Autodesk Fusion 360 part; units mm, degrees
(part 3 of 18)
  line L916 (69.5484, -103.959) -> (68.9847, -104.146)
  line L917 (27.4521, -121.483) -> (28.0455, -121.505)
  line L918 (185.518, -120.817) -> (186.059, -120.571)
  line L919 (19.2578, -114.105) -> (19.3803, -114.686)
  line L920 (174.55, -117.401) -> (174.888, -117.889)
  line L921 (174.245, -116.891) -> (174.55, -117.401)
  line L922 (180.861, -121.422) -> (181.452, -121.483)
  line L923 (179.699, -121.183) -> (180.276, -121.322)
  line L924 (70.7068, -103.7) -> (70.1233, -103.811)
  line L925 (180.276, -121.322) -> (180.861, -121.422)
  line L926 (19.3803, -114.686) -> (19.541, -115.258)
  line L927 (64.17, -108.346) -> (63.9088, -108.879)
  line L928 (29.8346, -121.428) -> (29.2581, -121.523)
  line L929 (183.663, -103.737) -> (183.075, -103.651)
  line L930 (28.0926, -121.6) -> (27.5085, -121.582)
  line L931 (184.243, -103.861) -> (183.663, -103.737)
  line L932 (176.417, -105.61) -> (175.97, -106.001)
  line L933 (176.889, -105.251) -> (176.417, -105.61)
  line L934 (177.385, -104.923) -> (176.889, -105.251)
  line L935 (19.3817, -115.06) -> (19.2379, -114.493)
  line L936 (27.5085, -121.582) -> (26.9269, -121.527)
  line L937 (64.7955, -107.337) -> (64.466, -107.831)
  line L938 (188.753, -106.581) -> (188.342, -106.152)
  line L939 (182.093, -121.6) -> (181.509, -121.582)
  line L940 (182.677, -121.58) -> (182.093, -121.6)
  line L941 (29.8162, -121.334) -> (30.3945, -121.2)
  line L942 (180.35, -121.434) -> (179.78, -121.304)
  line L943 (180.927, -121.527) -> (180.35, -121.434)
  line L944 (181.509, -121.582) -> (180.927, -121.527)
  line L945 (76.4456, -104.733) -> (75.9179, -104.461)
  line L946 (33.9903, -119.401) -> (33.5358, -119.768)
  line L947 (173.562, -115.616) -> (173.382, -115.06)
  line L948 (63.2379, -114.493) -> (63.1309, -113.919)
  line L949 (21.8816, -105.953) -> (22.3203, -105.567)
  line L950 (63.1309, -113.919) -> (63.0612, -113.339)
  line L951 (35.8585, -117.17) -> (35.5441, -117.663)
  line L952 (32.0441, -120.684) -> (31.5109, -120.923)
  line L953 (72.0926, -121.6) -> (71.5085, -121.582)
  line L954 (72.6766, -121.58) -> (72.0926, -121.6)
  line L955 (19.541, -115.258) -> (19.7392, -115.817)
  line L956 (189.133, -107.037) -> (188.753, -106.581)
  line L957 (181.889, -103.597) -> (181.296, -103.629)
  line L958 (182.483, -103.604) -> (181.889, -103.597)
  line L959 (183.075, -103.651) -> (182.483, -103.604)
  line L960 (173.238, -114.493) -> (173.131, -113.919)
  line L961 (173.382, -115.06) -> (173.238, -114.493)
  line L962 (175.657, -118.793) -> (176.085, -119.205)
  line L963 (174.888, -117.889) -> (175.257, -118.354)
  line L964 (72.483, -103.604) -> (71.8893, -103.597)
  line L965 (175.257, -118.354) -> (175.657, -118.793)
  line L966 (19.1309, -113.919) -> (19.0612, -113.339)
  line L967 (28.0455, -121.505) -> (28.6391, -121.487)
  line L968 (179.22, -121.137) -> (178.672, -120.935)
  line L969 (179.78, -121.304) -> (179.22, -121.137)
  line L970 (173.061, -113.339) -> (173.029, -112.755)
  line L971 (173.131, -113.919) -> (173.061, -113.339)
  line L972 (173.029, -112.755) -> (173.033, -112.331)
  line L973 (74.2432, -103.861) -> (73.6626, -103.737)
  line L974 (24.672, -120.935) -> (24.138, -120.698)
  line L975 (19.7774, -116.159) -> (19.5618, -115.616)
  line L976 (189.544, -117.663) -> (189.199, -118.134)
  line L977 (65.7561, -119.027) -> (65.3513, -118.606)
  line L978 (66.1873, -119.421) -> (65.7561, -119.027)
  line L979 (65.3513, -118.606) -> (64.9746, -118.159)
  line L980 (21.0836, -106.806) -> (21.4688, -106.366)
  line L981 (30.4039, -121.296) -> (29.8346, -121.428)
  line L982 (36.8266, -110.238) -> (36.9575, -110.808)
  line L983 (77.5358, -119.768) -> (77.0587, -120.105)
  line L984 (70.35, -121.434) -> (69.7803, -121.304)
  line L985 (70.9269, -121.527) -> (70.35, -121.434)
  line L986 (77.9903, -119.401) -> (77.5358, -119.768)
  line L987 (71.5085, -121.582) -> (70.9269, -121.527)
  line L988 (20.402, -107.754) -> (20.7274, -107.269)
  line L989 (36.6591, -109.678) -> (36.8266, -110.238)
  line L990 (36.4559, -109.131) -> (36.6591, -109.678)
  line L991 (80.7806, -115.029) -> (80.6024, -115.586)
  line L992 (80.9224, -114.462) -> (80.7806, -115.029)
  line L993 (76.0441, -120.684) -> (75.5109, -120.923)
  line L994 (76.5607, -120.411) -> (76.0441, -120.684)
  line L995 (77.0587, -120.105) -> (76.5607, -120.411)
  line L996 (19.8482, -108.783) -> (20.1085, -108.26)
  line L997 (31.5109, -120.923) -> (30.9634, -121.127)
  line L998 (80.6591, -109.678) -> (80.8266, -110.238)
  line L999 (30.9634, -121.127) -> (30.4039, -121.296)
  line L1000 (80.4559, -109.131) -> (80.6591, -109.678)
  line L1001 (80.3887, -116.13) -> (80.1404, -116.659)
  line L1002 (80.6024, -115.586) -> (80.3887, -116.13)
  line L1003 (80.1404, -116.659) -> (79.8585, -117.17)
  line L1004 (19.4315, -109.874) -> (19.6222, -109.322)
  line L1005 (22.539, -119.587) -> (23.0175, -119.939)
  line L1006 (23.0175, -119.939) -> (23.5183, -120.258)
  line L1007 (77.2028, -105.092) -> (77.6734, -105.438)
  line L1008 (81.0514, -111.384) -> (81.1079, -111.966)
  line L1009 (80.9575, -110.808) -> (81.0514, -111.384)
  line L1010 (76.7108, -104.776) -> (77.2028, -105.092)
  line L1011 (80.8266, -110.238) -> (80.9575, -110.808)
  line L1012 (23.5183, -120.258) -> (24.0392, -120.543)
  line L1013 (19.0612, -113.339) -> (19.0291, -112.755)
  line L1014 (19.1589, -111.01) -> (19.2769, -110.437)
  line L1015 (71.682, -103.509) -> (72.2663, -103.502)
  line L1016 (71.0994, -103.553) -> (71.682, -103.509)
  line L1017 (78.5428, -106.218) -> (78.9379, -106.649)
  line L1018 (78.1207, -105.814) -> (78.5428, -106.218)
  line L1019 (63.1297, -112.925) -> (63.1742, -113.517)
  line L1020 (19.0291, -112.755) -> (19.0332, -112.331)
  line L1021 (77.6734, -105.438) -> (78.1207, -105.814)
  line L1022 (24.0392, -120.543) -> (24.5778, -120.793)
  line L1023 (66.3203, -105.567) -> (66.7829, -105.21)
  line L1024 (65.8816, -105.953) -> (66.3203, -105.567)
  line L1025 (73.4301, -103.602) -> (74.0047, -103.708)
  line L1026 (72.2663, -103.502) -> (72.8498, -103.533)
  line L1027 (63.1587, -111.738) -> (63.1245, -112.331)
  line L1028 (72.8498, -103.533) -> (73.4301, -103.602)
  line L1029 (63.2769, -110.437) -> (63.4315, -109.874)
  line L1030 (63.1589, -111.01) -> (63.2769, -110.437)
  line L1031 (67.7724, -104.589) -> (68.2951, -104.328)
  line L1032 (67.2676, -104.884) -> (67.7724, -104.589)
  line L1033 (66.7829, -105.21) -> (67.2676, -104.884)
  line L1034 (63.3443, -110.566) -> (63.232, -111.149)
  line L1035 (19.0347, -112.171) -> (19.078, -111.588)
  line L1036 (173.909, -108.879) -> (173.683, -109.429)
  line L1037 (19.0332, -112.331) -> (19.0347, -112.171)
  line L1038 (174.17, -108.346) -> (173.909, -108.879)
  line L1039 (63.6222, -109.322) -> (63.8482, -108.783)
  line L1040 (63.4315, -109.874) -> (63.6222, -109.322)
  line L1041 (63.8482, -108.783) -> (64.1085, -108.26)
  line L1042 (37.1079, -64.566) -> (37.1268, -65.15)
  line L1043 (36.8847, -66.7665) -> (36.9725, -66.1793)
  line L1044 (36.7582, -67.3467) -> (36.8847, -66.7665)
  line L1045 (33.0844, -72.574) -> (33.5654, -72.2258)
  line L1046 (35.8785, -69.546) -> (36.1527, -69.0193)
  line L1047 (36.7806, -67.6293) -> (36.6024, -68.1858)
  line L1048 (25.2202, -73.7373) -> (24.672, -73.5351)
  line L1049 (35.5441, -70.263) -> (35.1986, -70.7342)
  line L1050 (35.8585, -69.7704) -> (35.5441, -70.263)
  line L1051 (36.9575, -63.4077) -> (37.0514, -63.9844)
  line L1052 (28.6766, -74.1801) -> (28.0926, -74.2)
  line L1053 (36.1404, -69.2586) -> (35.8585, -69.7704)
  line L1054 (37.0514, -63.9844) -> (37.1079, -64.566)
  line L1055 (29.2581, -74.1226) -> (28.6766, -74.1801)
  line L1056 (27.5085, -74.1821) -> (26.9269, -74.1266)
  line L1057 (30.9634, -73.7273) -> (30.4039, -73.8957)
  line L1058 (32.0441, -73.2841) -> (31.5109, -73.5231)
  line L1059 (33.6734, -58.038) -> (34.1207, -58.414)
  line L1060 (36.6591, -62.2784) -> (36.8266, -62.8382)
  line L1061 (28.0926, -74.2) -> (27.5085, -74.1821)
  line L1062 (29.8346, -74.0276) -> (29.2581, -74.1226)
  line L1063 (20.3113, -69.7975) -> (20.0276, -69.2867)
  line L1064 (23.6204, -73.0267) -> (23.1214, -72.7227)
  line L1065 (35.3045, -59.7036) -> (35.6409, -60.1813)
  line L1066 (25.3856, -56.5094) -> (25.9488, -56.3538)
  line L1067 (37.0951, -65.9073) -> (37.0274, -66.4877)
  line L1068 (36.1527, -69.0193) -> (36.3914, -68.4756)
  line L1069 (36.9224, -67.0625) -> (36.7806, -67.6293)
  line L1070 (37.0274, -66.4877) -> (36.9224, -67.0625)
  line L1071 (36.8266, -62.8382) -> (36.9575, -63.4077)
  line L1072 (25.9488, -56.3538) -> (26.5208, -56.2348)
  line L1073 (30.0047, -56.3077) -> (30.5713, -56.4506)
  line L1074 (19.8482, -61.3827) -> (20.1085, -60.8595)
  line L1075 (20.402, -60.3542) -> (20.7274, -59.869)
  line L1076 (34.5428, -58.818) -> (34.9379, -59.2485)
  line L1077 (22.1873, -72.0214) -> (21.7561, -71.627)
  line L1078 (36.6024, -68.1858) -> (36.3887, -68.7297)
  line L1079 (20.6274, -70.289) -> (20.3113, -69.7975)
  line L1080 (20.1085, -60.8595) -> (20.402, -60.3542)
  line L1081 (30.4039, -73.8957) -> (29.8346, -74.0276)
  line L1082 (27.682, -56.1086) -> (28.2663, -56.102)
  line L1083 (33.9903, -72.0008) -> (33.5358, -72.3681)
  line L1084 (35.1986, -70.7342) -> (34.8234, -71.1821)
  line L1085 (32.0585, -73.1711) -> (32.5813, -72.8896)
  line L1086 (24.8336, -56.7011) -> (25.3856, -56.5094)
  line L1087 (26.35, -74.0337) -> (25.7803, -73.9038)
  line L1088 (37.1268, -65.15) -> (37.1251, -65.3237)
  line L1089 (23.1214, -72.7227) -> (22.643, -72.3871)
  line L1090 (21.7561, -71.627) -> (21.3513, -71.2056)
  line L1091 (25.7803, -73.9038) -> (25.2202, -73.7373)
  line L1092 (35.6409, -60.1813) -> (35.9457, -60.6798)
  line L1093 (36.2178, -61.1969) -> (36.4559, -61.7305)
  line L1094 (21.3513, -71.2056) -> (20.9746, -70.759)
  line L1095 (19.7774, -68.7587) -> (19.5618, -68.2156)
  line L1096 (32.5607, -73.0111) -> (32.0441, -73.2841)
  line L1097 (36.3914, -68.4756) -> (36.5935, -67.9172)
  line L1098 (32.5813, -72.8896) -> (33.0844, -72.574)
  line L1099 (34.42, -71.6049) -> (33.9903, -72.0008)
  line L1100 (34.453, -71.4378) -> (34.8557, -71.0014)
  line L1101 (36.9725, -66.1793) -> (37.0211, -65.5875)
  line L1102 (26.9269, -74.1266) -> (26.35, -74.0337)
  line L1103 (34.0223, -71.8465) -> (34.453, -71.4378)
  line L1104 (31.5109, -73.5231) -> (30.9634, -73.7273)
  line L1105 (26.8615, -74.0221) -> (27.4521, -74.0832)
  line L1106 (109.882, -58.5528) -> (110.32, -58.1668)
  line L1107 (159.296, -56.2291) -> (158.707, -56.3004)
  line L1108 (19.541, -67.8577) -> (19.7392, -68.4175)
  line L1109 (33.5654, -72.2258) -> (34.0223, -71.8465)
  line L1110 (107.622, -61.9215) -> (107.848, -61.3827)
  line L1111 (27.0994, -56.1529) -> (27.682, -56.1086)
  line L1112 (25.6987, -73.7835) -> (26.2761, -73.9221)
  line L1113 (19.3817, -67.6597) -> (19.2379, -67.0934)
  line L1114 (24.138, -73.2979) -> (23.6204, -73.0267)
  line L1115 (19.5618, -68.2156) -> (19.3817, -67.6597)
  line L1116 (35.2286, -70.5393) -> (35.57, -70.0534)
  line L1117 (26.5208, -56.2348) -> (27.0994, -56.1529)
  line L1118 (36.3887, -68.7297) -> (36.1404, -69.2586)
  line L1119 (35.57, -70.0534) -> (35.8785, -69.546)
  line L1120 (32.1995, -57.0936) -> (32.7108, -57.3764)
  line L1121 (20.0276, -69.2867) -> (19.7774, -68.7587)
  line L1122 (37.1251, -65.3237) -> (37.0951, -65.9073)
  line L1123 (22.643, -72.3871) -> (22.1873, -72.0214)
  line L1124 (33.0587, -72.7054) -> (32.5607, -73.0111)
  line L1125 (36.5935, -67.9172) -> (36.7582, -67.3467)
  line L1126 (34.8234, -71.1821) -> (34.42, -71.6049)
  line L1127 (34.8557, -71.0014) -> (35.2286, -70.5393)
  line L1128 (19.0347, -64.771) -> (19.078, -64.1883)
  line L1129 (33.5358, -72.3681) -> (33.0587, -72.7054)
  line L1130 (20.9746, -70.759) -> (20.6274, -70.289)
  line L1131 (35.4833, -60.1165) -> (35.1334, -59.6368)
  line L1132 (24.672, -73.5351) -> (24.138, -73.2979)
  line L1133 (19.0332, -64.9312) -> (19.0347, -64.771)
  line L1134 (19.1742, -66.1171) -> (19.2578, -66.705)
  line L1135 (109.469, -58.9664) -> (109.882, -58.5528)
  line L1136 (19.1309, -66.5189) -> (19.0612, -65.9388)
  line L1137 (107.848, -61.3827) -> (108.108, -60.8595)
  line L1138 (29.8162, -73.9345) -> (30.3945, -73.7999)
  line L1139 (19.0291, -65.3553) -> (19.0332, -64.9312)
  line L1140 (19.0612, -65.9388) -> (19.0291, -65.3553)
  line L1141 (28.6391, -74.0873) -> (29.2302, -74.0304)
  line L1142 (27.4521, -74.0832) -> (28.0455, -74.1049)
  line L1143 (19.2578, -66.705) -> (19.3803, -67.2861)
  line L1144 (35.1334, -59.6368) -> (34.7525, -59.1812)
  line L1145 (19.7392, -68.4175) -> (19.9741, -68.9629)
  line L1146 (19.9741, -68.9629) -> (20.2446, -69.4915)
  line L1147 (20.5495, -70.001) -> (20.8876, -70.4892)
  line L1148 (108.727, -59.869) -> (109.084, -59.4057)
  line L1149 (21.2572, -70.9539) -> (21.6569, -71.3931)
  line L1150 (37.0121, -64.5565) -> (36.9531, -63.9656)
  line L1151 (36.9531, -63.9656) -> (36.8551, -63.38)
  line L1152 (109.084, -59.4057) -> (109.469, -58.9664)
  line L1153 (30.8143, -56.6237) -> (30.2432, -56.461)
  line L1154 (20.2446, -69.4915) -> (20.5495, -70.001)
  line L1155 (36.084, -61.1403) -> (35.8006, -60.6185)
  line L1156 (32.954, -57.6397) -> (32.4456, -57.333)
  line L1157 (21.6569, -71.3931) -> (22.0847, -71.8049)
  line L1158 (33.9045, -58.3507) -> (33.4411, -57.9794)
  line L1159 (107.432, -62.4738) -> (107.622, -61.9215)
  line L1160 (19.2379, -67.0934) -> (19.1309, -66.5189)
  line L1161 (36.8551, -63.38) -> (36.7185, -62.8021)
  line L1162 (27.8893, -56.197) -> (27.2963, -56.2291)
  line L1163 (30.2432, -56.461) -> (29.6626, -56.3365)
  line L1164 (108.402, -60.3542) -> (108.727, -59.869)
  line L1165 (32.4456, -57.333) -> (31.9179, -57.0606)
  line L1166 (153.97, -58.6007) -> (153.549, -59.0199)
  line L1167 (26.7068, -56.3004) -> (26.1233, -56.4107)
  line L1168 (24.4345, -56.9692) -> (23.9003, -57.2286)
  line L1169 (151.232, -63.7491) -> (151.159, -64.3384)
  line L1170 (19.2769, -63.0373) -> (19.4315, -62.4738)
  line L1171 (155.385, -57.5228) -> (154.889, -57.8505)
  line L1172 (158.123, -56.4107) -> (157.548, -56.5593)
  line L1173 (153.549, -59.0199) -> (153.157, -59.466)
  line L1174 (26.1233, -56.4107) -> (25.5484, -56.5593)
  line L1175 (157.548, -56.5593) -> (156.985, -56.7458)
  line L1176 (19.6222, -61.9215) -> (19.8482, -61.3827)
  line L1177 (108.108, -60.8595) -> (108.402, -60.3542)
  line L1178 (19.4315, -62.4738) -> (19.6222, -61.9215)
  line L1179 (152.795, -59.9371) -> (152.466, -60.4311)
  line L1180 (27.2963, -56.2291) -> (26.7068, -56.3004)
  line L1181 (23.3845, -57.5228) -> (22.8893, -57.8505)
  line L1182 (29.6626, -56.3365) -> (29.075, -56.2508)
  line L1183 (31.9179, -57.0606) -> (31.3734, -56.8239)
  line L1184 (151.124, -64.9312) -> (151.13, -65.525)
  line L1185 (23.9003, -57.2286) -> (23.3845, -57.5228)
  line L1186 (151.344, -63.166) -> (151.232, -63.7491)
  line L1187 (151.159, -64.3384) -> (151.124, -64.9312)
  line L1188 (22.8893, -57.8505) -> (22.417, -58.2104)
  line L1189 (31.3734, -56.8239) -> (30.8143, -56.6237)
  line L1190 (37.0318, -65.15) -> (37.0121, -64.5565)
  line L1191 (160.483, -56.2042) -> (159.889, -56.197)
  line L1192 (24.9847, -56.7458) -> (24.4345, -56.9692)
  line L1193 (25.5484, -56.5593) -> (24.9847, -56.7458)
  line L1194 (30.9627, -73.6272) -> (31.5182, -73.4173)
  line L1195 (23.0175, -72.5389) -> (23.5183, -72.8579)
  line L1196 (31.5182, -73.4173) -> (32.0585, -73.1711)
  line L1197 (29.2302, -74.0304) -> (29.8162, -73.9345)
  line L1198 (22.417, -58.2104) -> (21.9695, -58.6007)
  line L1199 (156.985, -56.7458) -> (156.434, -56.9692)
  line L1200 (22.0847, -71.8049) -> (22.539, -72.1873)
  line L1201 (151.495, -62.5917) -> (151.344, -63.166)
  line L1202 (28.483, -56.2042) -> (27.8893, -56.197)
  line L1203 (19.3443, -63.166) -> (19.232, -63.7491)
  line L1204 (19.232, -63.7491) -> (19.1587, -64.3384)
  line L1205 (30.3945, -73.7999) -> (30.9627, -73.6272)
  line L1206 (19.1297, -65.525) -> (19.1742, -66.1171)
  line L1207 (151.909, -61.4791) -> (151.683, -62.0285)
  line L1208 (19.495, -62.5917) -> (19.3443, -63.166)
  line L1209 (154.889, -57.8505) -> (154.417, -58.2104)
  line L1210 (153.157, -59.466) -> (152.795, -59.9371)
  line L1211 (26.2761, -73.9221) -> (26.8615, -74.0221)
  line L1212 (19.078, -64.1883) -> (19.1589, -63.6096)
  line L1213 (107.159, -63.6096) -> (107.277, -63.0373)
  line L1214 (19.1245, -64.9312) -> (19.1297, -65.525)
  line L1215 (20.7955, -59.9371) -> (20.466, -60.4311)
  line L1216 (152.466, -60.4311) -> (152.17, -60.9459)
  line L1217 (19.1587, -64.3384) -> (19.1245, -64.9312)
  line L1218 (19.1589, -63.6096) -> (19.2769, -63.0373)
  line L1219 (21.9695, -58.6007) -> (21.5489, -59.0199)
  line L1220 (151.683, -62.0285) -> (151.495, -62.5917)
  line L1221 (22.539, -72.1873) -> (23.0175, -72.5389)
  line L1222 (20.8876, -70.4892) -> (21.2572, -70.9539)
  line L1223 (107.277, -63.0373) -> (107.432, -62.4738)
  line L1224 (23.5183, -72.8579) -> (24.0392, -73.1431)
  line L1225 (25.1318, -73.6069) -> (25.6987, -73.7835)
  line L1226 (154.417, -58.2104) -> (153.97, -58.6007)
  line L1227 (158.707, -56.3004) -> (158.123, -56.4107)
  line L1228 (21.157, -59.466) -> (20.7955, -59.9371)
  line L1229 (21.5489, -59.0199) -> (21.157, -59.466)
  line L1230 (152.17, -60.9459) -> (151.909, -61.4791)
  line L1231 (34.3423, -58.7519) -> (33.9045, -58.3507)
  line L1232 (28.0455, -74.1049) -> (28.6391, -74.0873)
  line L1233 (24.5778, -73.3931) -> (25.1318, -73.6069)
  line L1234 (34.7525, -59.1812) -> (34.3423, -58.7519)
  line L1235 (23.2676, -57.4835) -> (23.7724, -57.1892)
  line L1236 (29.4301, -56.2018) -> (30.0047, -56.3077)
  line L1237 (31.671, -56.8443) -> (32.1995, -57.0936)
  line L1238 (24.0392, -73.1431) -> (24.5778, -73.3931)
  line L1239 (19.3803, -67.2861) -> (19.541, -67.8577)
  line L1240 (107.078, -64.1883) -> (107.159, -63.6096)
  line L1241 (33.4411, -57.9794) -> (32.954, -57.6397)
  line L1242 (34.1207, -58.414) -> (34.5428, -58.818)
  line L1243 (28.2663, -56.102) -> (28.8498, -56.1331)
  line L1244 (31.1275, -56.6297) -> (31.671, -56.8443)
  line L1245 (110.32, -58.1668) -> (110.783, -57.8099)
  line L1246 (36.4559, -61.7305) -> (36.6591, -62.2784)
  line L1247 (34.9379, -59.2485) -> (35.3045, -59.7036)
  line L1248 (22.7829, -57.8099) -> (23.2676, -57.4835)
  line L1249 (35.9457, -60.6798) -> (36.2178, -61.1969)
  line L1250 (30.5713, -56.4506) -> (31.1275, -56.6297)
  line L1251 (28.8498, -56.1331) -> (29.4301, -56.2018)
  line L1252 (21.4688, -58.9664) -> (21.8816, -58.5528)
  line L1253 (21.8816, -58.5528) -> (22.3203, -58.1668)
  line L1254 (155.9, -57.2286) -> (155.385, -57.5228)
  line L1255 (36.3321, -61.6798) -> (36.084, -61.1403)
  line L1256 (35.8006, -60.6185) -> (35.4833, -60.1165)
  line L1257 (33.2028, -57.6917) -> (33.6734, -58.038)
  line L1258 (22.3203, -58.1668) -> (22.7829, -57.8099)
  line L1259 (20.7274, -59.869) -> (21.0836, -59.4057)
  line L1260 (21.0836, -59.4057) -> (21.4688, -58.9664)
  line L1261 (36.5439, -62.2345) -> (36.3321, -61.6798)
  line L1262 (36.7185, -62.8021) -> (36.5439, -62.2345)
  line L1263 (32.7108, -57.3764) -> (33.2028, -57.6917)
  line L1264 (159.889, -56.197) -> (159.296, -56.2291)
  line L1265 (24.2951, -56.928) -> (24.8336, -56.7011)
  line L1266 (23.7724, -57.1892) -> (24.2951, -56.928)
  line L1267 (29.075, -56.2508) -> (28.483, -56.2042)
  line L1268 (37.0211, -65.5875) -> (37.0318, -65.15)
  line L1269 (151.13, -65.525) -> (151.174, -66.1171)
  line L1270 (156.434, -56.9692) -> (155.9, -57.2286)
  line L1271 (52.4039, -50.1957) -> (51.8346, -50.3276)
  line L1272 (156.138, -49.5979) -> (155.62, -49.3267)
  line L1273 (156.672, -49.8351) -> (156.138, -49.5979)
  line L1274 (80.5439, -38.5345) -> (80.3321, -37.9798)
  line L1275 (76.954, -33.9397) -> (76.4456, -33.633)
  line L1276 (75.9179, -33.3606) -> (75.3734, -33.1239)
  line L1277 (56.42, -47.9049) -> (55.9903, -48.3008)
  line L1278 (153.882, -34.8528) -> (154.32, -34.4668)
  line L1279 (154.32, -34.4668) -> (154.783, -34.1099)
  line L1280 (163.671, -33.1443) -> (164.199, -33.3936)
  line L1281 (58.2178, -37.4969) -> (58.4559, -38.0305)
  line L1282 (160.677, -50.4801) -> (160.093, -50.5)
  line L1283 (72.0926, -50.5) -> (71.5085, -50.4821)
  line L1284 (78.3423, -35.0519) -> (77.9045, -34.6507)
  line L1285 (42.0276, -45.5867) -> (41.7774, -45.0587)
  line L1286 (58.7806, -43.9293) -> (58.6024, -44.4858)
  line L1287 (73.075, -32.5508) -> (72.483, -32.5042)
  line L1288 (79.5441, -46.563) -> (79.1986, -47.0342)
  line L1289 (69.5484, -32.8593) -> (68.9847, -33.0458)
  line L1290 (167.544, -46.563) -> (167.199, -47.0342)
  line L1291 (70.7068, -32.6004) -> (70.1233, -32.7107)
  line L1292 (166.121, -34.714) -> (166.543, -35.118)
  line L1293 (168.218, -37.4969) -> (168.456, -38.0305)
  line L1294 (51.2581, -50.4226) -> (50.6766, -50.4801)
  line L1295 (73.6626, -32.6365) -> (73.075, -32.5508)
  line L1296 (65.2572, -47.2539) -> (65.6569, -47.6931)
  line L1297 (79.8585, -46.0704) -> (79.5441, -46.563)
  line L1298 (59.0514, -40.2844) -> (59.1079, -40.866)
  line L1299 (55.5358, -48.6681) -> (55.0587, -49.0054)
  line L1300 (51.075, -32.5508) -> (50.483, -32.5042)
  line L1301 (46.9847, -33.0458) -> (46.4345, -33.2692)
  line L1302 (58.6591, -38.5784) -> (58.8266, -39.1382)
  line L1303 (52.8143, -32.9237) -> (52.2432, -32.761)
  line L1304 (63.232, -40.0491) -> (63.1587, -40.6384)
  line L1305 (164.199, -33.3936) -> (164.711, -33.6764)
  line L1306 (56.8557, -47.3014) -> (57.2286, -46.8393)
  line L1307 (47.7803, -50.2038) -> (47.2202, -50.0373)
  line L1308 (54.954, -33.9397) -> (54.4456, -33.633)
  line L1309 (167.858, -46.0704) -> (167.544, -46.563)
  line L1310 (54.5607, -49.3111) -> (54.0441, -49.5841)
  line L1311 (55.9045, -34.6507) -> (55.4411, -34.2794)
  line L1312 (59.0274, -42.7877) -> (58.9224, -43.3625)
  line L1313 (78.7525, -35.4812) -> (78.3423, -35.0519)
  line L1314 (165.203, -33.9917) -> (165.673, -34.338)
  line L1315 (80.3887, -45.0297) -> (80.1404, -45.5586)
  line L1316 (164.711, -33.6764) -> (165.203, -33.9917)
  line L1317 (163.128, -32.9297) -> (163.671, -33.1443)
  line L1318 (57.5441, -46.563) -> (57.1986, -47.0342)
  line L1319 (52.9634, -50.0273) -> (52.4039, -50.1957)
  line L1320 (59.0951, -42.2073) -> (59.0274, -42.7877)
  line L1321 (157.386, -32.8094) -> (157.949, -32.6538)
  line L1322 (63.1742, -42.4171) -> (63.2578, -43.005)
  line L1323 (69.6987, -50.0835) -> (70.2761, -50.2221)
  line L1324 (58.7582, -43.6467) -> (58.8847, -43.0665)
  line L1325 (75.1275, -32.9297) -> (75.671, -33.1443)
  line L1326 (166.543, -35.118) -> (166.938, -35.5485)
  line L1327 (80.8266, -39.1382) -> (80.9575, -39.7077)
  line L1328 (63.1245, -41.2312) -> (63.1297, -41.825)
  line L1329 (58.9224, -43.3625) -> (58.7806, -43.9293)
  line L1330 (72.483, -32.5042) -> (71.8893, -32.497)
  line L1331 (53.9179, -33.3606) -> (53.3734, -33.1239)
  line L1332 (66.1873, -48.3214) -> (65.7561, -47.927)
  line L1333 (59.1251, -41.6237) -> (59.0951, -42.2073)
  line L1334 (64.7955, -36.2371) -> (64.466, -36.7311)
  line L1335 (76.4456, -33.633) -> (75.9179, -33.3606)
  line L1336 (58.3887, -45.0297) -> (58.1404, -45.5586)
  line L1337 (54.4456, -33.633) -> (53.9179, -33.3606)
  line L1338 (165.673, -34.338) -> (166.121, -34.714)
  line L1339 (45.6204, -49.3267) -> (45.1214, -49.0227)
  line L1340 (55.4411, -34.2794) -> (54.954, -33.9397)
  line L1341 (44.643, -48.6871) -> (44.1873, -48.3214)
  line L1342 (162.005, -32.6077) -> (162.571, -32.7506)
  line L1343 (58.3914, -44.7756) -> (58.5935, -44.2172)
  line L1344 (168.391, -44.7756) -> (168.594, -44.2172)
  line L1345 (43.3513, -47.5056) -> (42.9746, -47.059)
  line L1346 (151.848, -37.6827) -> (152.108, -37.1595)
  line L1347 (68.8336, -33.0011) -> (69.3856, -32.8094)
  line L1348 (81.1079, -40.866) -> (81.1268, -41.45)
  line L1349 (162.571, -32.7506) -> (163.128, -32.9297)
  line L1350 (80.084, -37.4403) -> (79.8006, -36.9185)
  line L1351 (168.758, -43.6467) -> (168.885, -43.0665)
  line L1352 (46.4345, -33.2692) -> (45.9003, -33.5286)
  line L1353 (74.9627, -49.9272) -> (75.5182, -49.7173)
  line L1354 (152.727, -36.169) -> (153.084, -35.7057)
  line L1355 (63.495, -38.8917) -> (63.3443, -39.466)
  line L1356 (58.9725, -42.4793) -> (59.0211, -41.8875)
  line L1357 (63.7774, -45.0587) -> (63.5618, -44.5156)
  line L1358 (79.6409, -36.4813) -> (79.9457, -36.9798)
  line L1359 (151.562, -44.5156) -> (151.382, -43.9597)
  line L1360 (74.2432, -32.761) -> (73.6626, -32.6365)
  line L1361 (79.1334, -35.9368) -> (78.7525, -35.4812)
  line L1362 (78.1207, -34.714) -> (78.5428, -35.118)
  line L1363 (41.9741, -45.2629) -> (42.2446, -45.7915)
  line L1364 (168.957, -39.7077) -> (169.051, -40.2844)
  line L1365 (54.0585, -49.4711) -> (54.5813, -49.1896)
  line L1366 (79.1986, -47.0342) -> (78.8234, -47.4821)
  line L1367 (53.5109, -49.8231) -> (52.9634, -50.0273)
  line L1368 (75.3734, -33.1239) -> (74.8143, -32.9237)
  line L1369 (77.9045, -34.6507) -> (77.4411, -34.2794)
  line L1370 (76.0441, -49.5841) -> (75.5109, -49.8231)
  line L1371 (48.7068, -32.6004) -> (48.1233, -32.7107)
  line L1372 (45.9003, -33.5286) -> (45.3845, -33.8228)
  line L1373 (50.6391, -50.3873) -> (51.2302, -50.3304)
  line L1374 (168.922, -43.3625) -> (168.781, -43.9293)
  line L1375 (59.1268, -41.45) -> (59.1251, -41.6237)
  line L1376 (41.0291, -41.6553) -> (41.0332, -41.2312)
  line L1377 (153.351, -47.5056) -> (152.975, -47.059)
  line L1378 (74.9634, -50.0273) -> (74.4039, -50.1957)
  line L1379 (76.5607, -49.3111) -> (76.0441, -49.5841)
  line L1380 (55.5654, -48.5258) -> (56.0223, -48.1465)
  line L1381 (58.8847, -43.0665) -> (58.9725, -42.4793)
  line L1382 (154.643, -48.6871) -> (154.187, -48.3214)
  line L1383 (64.6274, -46.589) -> (64.3113, -46.0975)
  line L1384 (168.594, -44.2172) -> (168.758, -43.6467)
  line L1385 (49.4521, -50.3832) -> (50.0455, -50.4049)
  line L1386 (151.033, -41.2312) -> (151.035, -41.071)
  line L1387 (151.739, -44.7175) -> (151.974, -45.2629)
  line L1388 (77.0844, -48.874) -> (77.5654, -48.5258)
  line L1389 (41.2578, -43.005) -> (41.3803, -43.5861)
  line L1390 (167.229, -46.8393) -> (167.57, -46.3534)
  line L1391 (156.578, -49.6931) -> (157.132, -49.9069)
  line L1392 (155.772, -33.4892) -> (156.295, -33.228)
  line L1393 (65.6569, -47.6931) -> (66.0847, -48.1049)
  line L1394 (151.277, -39.3373) -> (151.432, -38.7738)
  line L1395 (64.5495, -46.301) -> (64.8876, -46.7892)
  line L1396 (161.43, -32.5018) -> (162.005, -32.6077)
  line L1397 (64.9746, -47.059) -> (64.6274, -46.589)
  line L1398 (152.108, -37.1595) -> (152.402, -36.6542)
  line L1399 (161.23, -50.3304) -> (161.816, -50.2345)
  line L1400 (165.565, -48.5258) -> (166.022, -48.1465)
  line L1401 (166.856, -47.3014) -> (167.229, -46.8393)
  line L1402 (163.518, -49.7173) -> (164.059, -49.4711)
  line L1403 (164.581, -49.1896) -> (165.084, -48.874)
  line L1404 (63.541, -44.1577) -> (63.7392, -44.7175)
  line L1405 (151.258, -43.005) -> (151.38, -43.5861)
  line L1406 (152.888, -46.7892) -> (153.257, -47.2539)
  line L1407 (162.963, -49.9272) -> (163.518, -49.7173)
  line L1408 (153.257, -47.2539) -> (153.657, -47.6931)
  line L1409 (152.55, -46.301) -> (152.888, -46.7892)
  line L1410 (168.153, -45.3193) -> (168.391, -44.7756)
  line L1411 (167.879, -45.846) -> (168.153, -45.3193)
  line L1412 (65.7561, -47.927) -> (65.3513, -47.5056)
  line L1413 (151.382, -43.9597) -> (151.238, -43.3934)
  line L1414 (152.311, -46.0975) -> (152.028, -45.5867)
  line L1415 (166.453, -47.7378) -> (166.856, -47.3014)
  line L1416 (167.57, -46.3534) -> (167.879, -45.846)
  line L1417 (152.975, -47.059) -> (152.627, -46.589)
  line L1418 (79.57, -46.3534) -> (79.8785, -45.846)
  line L1419 (152.245, -45.7915) -> (152.55, -46.301)
  line L1420 (160.639, -50.3873) -> (161.23, -50.3304)
  line L1421 (162.395, -50.0999) -> (162.963, -49.9272)
  line L1422 (157.132, -49.9069) -> (157.699, -50.0835)
  line L1423 (161.816, -50.2345) -> (162.395, -50.0999)
  line L1424 (151.974, -45.2629) -> (152.245, -45.7915)
  line L1425 (166.022, -48.1465) -> (166.453, -47.7378)
  line L1426 (151.541, -44.1577) -> (151.739, -44.7175)
  line L1427 (158.276, -50.2221) -> (158.861, -50.3221)
  line L1428 (158.861, -50.3221) -> (159.452, -50.3832)
  line L1429 (165.084, -48.874) -> (165.565, -48.5258)
  line L1430 (153.657, -47.6931) -> (154.085, -48.1049)
  line L1431 (157.22, -50.0373) -> (156.672, -49.8351)
  line L1432 (154.539, -48.4873) -> (155.018, -48.8389)
  line L1433 (58.8551, -39.68) -> (58.7185, -39.1021)
  line L1434 (81.0318, -41.45) -> (81.0121, -40.8565)
  line L1435 (57.8006, -36.9185) -> (57.4833, -36.4165)
  line L1436 (81.0514, -40.2844) -> (81.1079, -40.866)
  line L1437 (68.5778, -49.6931) -> (69.1318, -49.9069)
  line L1438 (63.1309, -42.8189) -> (63.0612, -42.2388)
  line L1439 (80.9575, -39.7077) -> (81.0514, -40.2844)
  line L1440 (155.018, -48.8389) -> (155.518, -49.1579)
  line L1441 (157.699, -50.0835) -> (158.276, -50.2221)
  line L1442 (155.518, -49.1579) -> (156.039, -49.4431)
  line L1443 (154.085, -48.1049) -> (154.539, -48.4873)
  line L1444 (160.046, -50.4049) -> (160.639, -50.3873)
  line L1445 (43.2572, -47.2539) -> (43.6569, -47.6931)
  line L1446 (162.963, -50.0273) -> (162.404, -50.1957)
  line L1447 (158.521, -32.5348) -> (159.099, -32.4529)
  line L1448 (69.3856, -32.8094) -> (69.9488, -32.6538)
  line L1449 (63.1587, -40.6384) -> (63.1245, -41.2312)
  line L1450 (58.5439, -38.5345) -> (58.3321, -37.9798)
  line L1451 (63.1589, -39.9096) -> (63.2769, -39.3373)
  line L1452 (64.8876, -46.7892) -> (65.2572, -47.2539)
  line L1453 (153.084, -35.7057) -> (153.469, -35.2664)
  line L1454 (57.57, -46.3534) -> (57.8785, -45.846)
  line L1455 (65.8816, -34.8528) -> (66.3203, -34.4668)
  line L1456 (72.2663, -32.402) -> (72.8498, -32.4331)
  line L1457 (42.5495, -46.301) -> (42.8876, -46.7892)
  line L1458 (58.3321, -37.9798) -> (58.084, -37.4403)
  line L1459 (51.8346, -50.3276) -> (51.2581, -50.4226)
  line L1460 (64.2446, -45.7915) -> (64.5495, -46.301)
  line L1461 (70.5208, -32.5348) -> (71.0994, -32.4529)
  line L1462 (56.7525, -35.4812) -> (56.3423, -35.0519)
  line L1463 (81.0121, -40.8565) -> (80.9531, -40.2656)
  line L1464 (54.0441, -49.5841) -> (53.5109, -49.8231)
  line L1465 (63.3817, -43.9597) -> (63.2379, -43.3934)
  line L1466 (64.17, -37.2459) -> (63.9088, -37.7791)
  line L1467 (66.539, -48.4873) -> (67.0175, -48.8389)
  line L1468 (153.469, -35.2664) -> (153.882, -34.8528)
  line L1469 (63.3443, -39.466) -> (63.232, -40.0491)
  line L1470 (65.9695, -34.9007) -> (65.5489, -35.3199)
  line L1471 (78.5428, -35.118) -> (78.9379, -35.5485)
  line L1472 (63.8482, -37.6827) -> (64.1085, -37.1595)
  line L1473 (68.0392, -49.4431) -> (68.5778, -49.6931)
  line L1474 (156.834, -33.0011) -> (157.386, -32.8094)
  line L1475 (50.0455, -50.4049) -> (50.6391, -50.3873)
  line L1476 (47.2202, -50.0373) -> (46.672, -49.8351)
  line L1477 (57.4833, -36.4165) -> (57.1334, -35.9368)
  line L1478 (64.466, -36.7311) -> (64.17, -37.2459)
  line L1479 (67.9003, -33.5286) -> (67.3845, -33.8228)
  line L1480 (58.7185, -39.1021) -> (58.5439, -38.5345)
  line L1481 (56.3423, -35.0519) -> (55.9045, -34.6507)
  line L1482 (68.2951, -33.228) -> (68.8336, -33.0011)
  line L1483 (73.8346, -50.3276) -> (73.2581, -50.4226)
  line L1484 (63.2769, -39.3373) -> (63.4315, -38.7738)
  line L1485 (66.3203, -34.4668) -> (66.7829, -34.1099)
  line L1486 (44.0847, -48.1049) -> (44.539, -48.4873)
  line L1487 (41.2321, -40.0491) -> (41.1587, -40.6384)
  line L1488 (64.402, -36.6542) -> (64.7274, -36.169)
  line L1489 (41.3443, -39.466) -> (41.2321, -40.0491)
  line L1490 (73.4301, -32.5018) -> (74.0047, -32.6077)
  line L1491 (44.417, -34.5104) -> (43.9695, -34.9007)
  line L1492 (151.061, -42.2388) -> (151.029, -41.6553)
  line L1493 (53.3734, -33.1239) -> (52.8143, -32.9237)
  line L1494 (162.404, -50.1957) -> (161.835, -50.3276)
  line L1495 (151.777, -45.0587) -> (151.562, -44.5156)
  line L1496 (70.35, -50.3337) -> (69.7803, -50.2038)
  line L1497 (64.7274, -36.169) -> (65.0836, -35.7057)
  line L1498 (58.1527, -45.3193) -> (58.3914, -44.7756)
  line L1499 (41.1297, -41.825) -> (41.1742, -42.4171)
  line L1500 (151.622, -38.2215) -> (151.848, -37.6827)
  line L1501 (63.0332, -41.2312) -> (63.0347, -41.071)
  line L1502 (49.2963, -32.5291) -> (48.7068, -32.6004)
  line L1503 (152.402, -36.6542) -> (152.727, -36.169)
  line L1504 (58.9575, -39.7077) -> (59.0514, -40.2844)
  line L1505 (63.9741, -45.2629) -> (64.2446, -45.7915)
  line L1506 (152.028, -45.5867) -> (151.777, -45.0587)
  line L1507 (72.6391, -50.3873) -> (73.2302, -50.3304)
  line L1508 (66.0847, -48.1049) -> (66.539, -48.4873)
  line L1509 (155.268, -33.7835) -> (155.772, -33.4892)
  line L1510 (59.1079, -40.866) -> (59.1268, -41.45)
  line L1511 (80.9224, -43.3625) -> (80.7806, -43.9293)
  line L1512 (41.3817, -43.9597) -> (41.2379, -43.3934)
  line L1513 (80.7185, -39.1021) -> (80.5439, -38.5345)
  line L1514 (73.2581, -50.4226) -> (72.6766, -50.4801)
  line L1515 (63.7392, -44.7175) -> (63.9741, -45.2629)
  line L1516 (64.1085, -37.1595) -> (64.402, -36.6542)
  line L1517 (155.121, -49.0227) -> (154.643, -48.6871)
  line L1518 (65.0836, -35.7057) -> (65.4688, -35.2664)
  line L1519 (81.0274, -42.7877) -> (80.9224, -43.3625)
  line L1520 (81.0951, -42.2073) -> (81.0274, -42.7877)
  line L1521 (59.0211, -41.8875) -> (59.0318, -41.45)
  line L1522 (151.238, -43.3934) -> (151.131, -42.8189)
  line L1523 (151.131, -42.8189) -> (151.061, -42.2388)
  line L1524 (51.2302, -50.3304) -> (51.8162, -50.2345)
  line L1525 (42.17, -37.2459) -> (41.9088, -37.7791)
  line L1526 (76.1995, -33.3936) -> (76.7108, -33.6764)
  line L1527 (71.2963, -32.5291) -> (70.7068, -32.6004)
  line L1528 (153.756, -47.927) -> (153.351, -47.5056)
  line L1529 (58.6024, -44.4858) -> (58.3887, -45.0297)
  line L1530 (81.1251, -41.6237) -> (81.0951, -42.2073)
  line L1531 (74.0047, -32.6077) -> (74.5713, -32.7506)
  line L1532 (45.1214, -49.0227) -> (44.643, -48.6871)
  line L1533 (71.8893, -32.497) -> (71.2963, -32.5291)
  line L1534 (80.1404, -45.5586) -> (79.8585, -46.0704)
  line L1535 (67.2676, -33.7835) -> (67.7724, -33.4892)
  line L1536 (66.643, -48.6871) -> (66.1873, -48.3214)
  line L1537 (75.671, -33.1443) -> (76.1995, -33.3936)
  line L1538 (43.9695, -34.9007) -> (43.5489, -35.3199)
  line L1539 (48.2761, -50.2221) -> (48.8615, -50.3221)
  line L1540 (41.6834, -38.3285) -> (41.495, -38.8917)
  line L1541 (42.466, -36.7311) -> (42.17, -37.2459)
  line L1542 (43.6569, -47.6931) -> (44.0847, -48.1049)
  line L1543 (159.509, -50.4821) -> (158.927, -50.4266)
  line L1544 (49.8893, -32.497) -> (49.2963, -32.5291)
  line L1545 (152.627, -46.589) -> (152.311, -46.0975)
  line L1546 (65.3513, -47.5056) -> (64.9746, -47.059)
  line L1547 (160.266, -32.402) -> (160.85, -32.4331)
  line L1548 (77.6734, -34.338) -> (78.1207, -34.714)
  line L1549 (76.5813, -49.1896) -> (77.0844, -48.874)
  line L1550 (66.8893, -34.1505) -> (66.417, -34.5104)
  line L1551 (81.1268, -41.45) -> (81.1251, -41.6237)
  line L1552 (64.3113, -46.0975) -> (64.0276, -45.5867)
  line L1553 (63.3803, -43.5861) -> (63.541, -44.1577)
  line L1554 (80.4559, -38.0305) -> (80.6591, -38.5784)
  line L1555 (79.8785, -45.846) -> (80.1527, -45.3193)
  line L1556 (81.0211, -41.8875) -> (81.0318, -41.45)
  line L1557 (80.2178, -37.4969) -> (80.4559, -38.0305)
  line L1558 (49.5085, -50.4821) -> (48.9269, -50.4266)
  line L1559 (46.0392, -49.4431) -> (46.5778, -49.6931)
  line L1560 (76.7108, -33.6764) -> (77.2028, -33.9917)
  line L1561 (70.8615, -50.3221) -> (71.4521, -50.3832)
  line L1562 (63.2578, -43.005) -> (63.3803, -43.5861)
  line L1563 (78.0223, -48.1465) -> (78.453, -47.7378)
  line L1564 (59.0121, -40.8565) -> (58.9531, -40.2656)
  line L1565 (41.2379, -43.3934) -> (41.1309, -42.8189)
  line L1566 (45.5183, -49.1579) -> (46.0392, -49.4431)
  line L1567 (72.6766, -50.4801) -> (72.0926, -50.5)
  line L1568 (80.8847, -43.0665) -> (80.9725, -42.4793)
  line L1569 (77.5654, -48.5258) -> (78.0223, -48.1465)
  line L1570 (71.0994, -32.4529) -> (71.682, -32.4086)
  line L1571 (80.5935, -44.2172) -> (80.7582, -43.6467)
  line L1572 (65.4688, -35.2664) -> (65.8816, -34.8528)
  line L1573 (168.456, -38.0305) -> (168.659, -38.5784)
  line L1574 (80.9531, -40.2656) -> (80.8551, -39.68)
  line L1575 (42.3113, -46.0975) -> (42.0276, -45.5867)
  line L1576 (78.9379, -35.5485) -> (79.3045, -36.0036)
  line L1577 (74.3945, -50.0999) -> (74.9627, -49.9272)
  line L1578 (41.7774, -45.0587) -> (41.5618, -44.5156)
  line L1579 (79.2286, -46.8393) -> (79.57, -46.3534)
  line L1580 (44.539, -48.4873) -> (45.0175, -48.8389)
  line L1581 (45.0175, -48.8389) -> (45.5183, -49.1579)
  line L1582 (63.0291, -41.6553) -> (63.0332, -41.2312)
  line L1583 (156.295, -33.228) -> (156.834, -33.0011)
  line L1584 (80.6591, -38.5784) -> (80.8266, -39.1382)
  line L1585 (65.5489, -35.3199) -> (65.157, -35.766)
  line L1586 (151.432, -38.7738) -> (151.622, -38.2215)
  line L1587 (68.9847, -33.0458) -> (68.4345, -33.2692)
  line L1588 (48.35, -50.3337) -> (47.7803, -50.2038)
  line L1589 (158.35, -50.3337) -> (157.78, -50.2038)
  line L1590 (50.6766, -50.4801) -> (50.0926, -50.5)
  line L1591 (58.8266, -39.1382) -> (58.9575, -39.7077)
  line L1592 (168.827, -39.1382) -> (168.957, -39.7077)
  line L1593 (41.1309, -42.8189) -> (41.0612, -42.2388)
  line L1594 (63.4315, -38.7738) -> (63.6222, -38.2215)
  line L1595 (42.8876, -46.7892) -> (43.2572, -47.2539)
  line L1596 (48.8615, -50.3221) -> (49.4521, -50.3832)
  line L1597 (165.536, -48.6681) -> (165.059, -49.0054)
  line L1598 (167.199, -47.0342) -> (166.823, -47.4821)
  line L1599 (41.1587, -40.6384) -> (41.1245, -41.2312)
  line L1600 (55.9903, -48.3008) -> (55.5358, -48.6681)
  line L1601 (42.9746, -47.059) -> (42.6274, -46.589)
  line L1602 (47.1318, -49.9069) -> (47.6987, -50.0835)
  line L1603 (151.078, -40.4883) -> (151.159, -39.9096)
  line L1604 (52.2432, -32.761) -> (51.6626, -32.6365)
  line L1605 (69.2202, -50.0373) -> (68.672, -49.8351)
  line L1606 (169.051, -40.2844) -> (169.108, -40.866)
  line L1607 (168.389, -45.0297) -> (168.14, -45.5586)
  line L1608 (53.5182, -49.7173) -> (54.0585, -49.4711)
  line L1609 (151.035, -41.071) -> (151.078, -40.4883)
  line L1610 (158.927, -50.4266) -> (158.35, -50.3337)
  line L1611 (168.659, -38.5784) -> (168.827, -39.1382)
  line L1612 (56.0223, -48.1465) -> (56.453, -47.7378)
  line L1613 (154.783, -34.1099) -> (155.268, -33.7835)
  line L1614 (78.453, -47.7378) -> (78.8557, -47.3014)
  line L1615 (63.6222, -38.2215) -> (63.8482, -37.6827)
  line L1616 (67.5183, -49.1579) -> (68.0392, -49.4431)
  line L1617 (41.541, -44.1577) -> (41.7392, -44.7175)
  line L1618 (73.8162, -50.2345) -> (74.3945, -50.0999)
  line L1619 (57.1334, -35.9368) -> (56.7525, -35.4812)
  line L1620 (69.1318, -49.9069) -> (69.6987, -50.0835)
  line L1621 (63.1297, -41.825) -> (63.1742, -42.4171)
  line L1622 (52.9627, -49.9272) -> (53.5182, -49.7173)
  line L1623 (78.8234, -47.4821) -> (78.42, -47.9049)
  line L1624 (168.602, -44.4858) -> (168.389, -45.0297)
  line L1625 (42.7955, -36.2371) -> (42.466, -36.7311)
  line L1626 (55.0844, -48.874) -> (55.5654, -48.5258)
  line L1627 (160.85, -32.4331) -> (161.43, -32.5018)
  line L1628 (58.4559, -38.0305) -> (58.6591, -38.5784)
  line L1629 (169.108, -40.866) -> (169.127, -41.45)
  line L1630 (169.027, -42.7877) -> (168.922, -43.3625)
  line L1631 (77.0587, -49.0054) -> (76.5607, -49.3111)
  line L1632 (77.5358, -48.6681) -> (77.0587, -49.0054)
  line L1633 (47.5484, -32.8593) -> (46.9847, -33.0458)
  line L1634 (70.9269, -50.4266) -> (70.35, -50.3337)
  line L1635 (67.6204, -49.3267) -> (67.1214, -49.0227)
  line L1636 (165.99, -48.3008) -> (165.536, -48.6681)
  line L1637 (169.095, -42.2073) -> (169.027, -42.7877)
  line L1638 (151.029, -41.6553) -> (151.033, -41.2312)
  line L1639 (56.453, -47.7378) -> (56.8557, -47.3014)
  line L1640 (54.5813, -49.1896) -> (55.0844, -48.874)
  line L1641 (167.641, -36.4813) -> (167.946, -36.9798)
  line L1642 (74.4039, -50.1957) -> (73.8346, -50.3276)
  line L1643 (169.125, -41.6237) -> (169.095, -42.2073)
  line L1644 (75.5109, -49.8231) -> (74.9634, -50.0273)
  line L1645 (63.5618, -44.5156) -> (63.3817, -43.9597)
  line L1646 (166.42, -47.9049) -> (165.99, -48.3008)
  line L1647 (43.7561, -47.927) -> (43.3513, -47.5056)
  line L1648 (164.561, -49.3111) -> (164.044, -49.5841)
  line L1649 (77.4411, -34.2794) -> (76.954, -33.9397)
  line L1650 (161.258, -50.4226) -> (160.677, -50.4801)
  line L1651 (69.7803, -50.2038) -> (69.2202, -50.0373)
  line L1652 (164.059, -49.4711) -> (164.581, -49.1896)
  line L1653 (57.8785, -45.846) -> (58.1527, -45.3193)
  line L1654 (43.157, -35.766) -> (42.7955, -36.2371)
  line L1655 (79.8006, -36.9185) -> (79.4833, -36.4165)
  line L1656 (68.672, -49.8351) -> (68.138, -49.5979)
  line L1657 (80.8551, -39.68) -> (80.7185, -39.1021)
  line L1658 (78.42, -47.9049) -> (77.9903, -48.3008)
  line L1659 (59.0318, -41.45) -> (59.0121, -40.8565)
  line L1660 (168.14, -45.5586) -> (167.858, -46.0704)
  line L1661 (41.9088, -37.7791) -> (41.6834, -38.3285)
  line L1662 (164.044, -49.5841) -> (163.511, -49.8231)
  line L1663 (57.8585, -46.0704) -> (57.5441, -46.563)
  line L1664 (57.2286, -46.8393) -> (57.57, -46.3534)
  line L1665 (46.672, -49.8351) -> (46.138, -49.5979)
  line L1666 (155.62, -49.3267) -> (155.121, -49.0227)
  line L1667 (55.0587, -49.0054) -> (54.5607, -49.3111)
  line L1668 (165.059, -49.0054) -> (164.561, -49.3111)
  line L1669 (44.1873, -48.3214) -> (43.7561, -47.927)
  line L1670 (68.138, -49.5979) -> (67.6204, -49.3267)
  line L1671 (51.8162, -50.2345) -> (52.3945, -50.0999)
  line L1672 (41.495, -38.8917) -> (41.3443, -39.466)
  line L1673 (46.138, -49.5979) -> (45.6204, -49.3267)
  line L1674 (167.946, -36.9798) -> (168.218, -37.4969)
  line L1675 (166.823, -47.4821) -> (166.42, -47.9049)
  line L1676 (167.304, -36.0036) -> (167.641, -36.4813)
  line L1677 (169.127, -41.45) -> (169.125, -41.6237)
  line L1678 (156.039, -49.4431) -> (156.578, -49.6931)
  line L1679 (58.9531, -40.2656) -> (58.8551, -39.68)
  line L1680 (168.781, -43.9293) -> (168.602, -44.4858)
  line L1681 (157.949, -32.6538) -> (158.521, -32.5348)
  line L1682 (163.511, -49.8231) -> (162.963, -50.0273)
  line L1683 (151.38, -43.5861) -> (151.541, -44.1577)
  line L1684 (58.1404, -45.5586) -> (57.8585, -46.0704)
  line L1685 (77.9903, -48.3008) -> (77.5358, -48.6681)
  line L1686 (43.5489, -35.3199) -> (43.157, -35.766)
  line L1687 (80.3321, -37.9798) -> (80.084, -37.4403)
  line L1688 (166.938, -35.5485) -> (167.304, -36.0036)
  line L1689 (67.3845, -33.8228) -> (66.8893, -34.1505)
  line L1690 (41.0332, -41.2312) -> (41.0347, -41.071)
  line L1691 (41.0347, -41.071) -> (41.078, -40.4883)
  line L1692 (67.7724, -33.4892) -> (68.2951, -33.228)
  line L1693 (66.417, -34.5104) -> (65.9695, -34.9007)
  line L1694 (67.1214, -49.0227) -> (66.643, -48.6871)
  line L1695 (41.3803, -43.5861) -> (41.541, -44.1577)
  line L1696 (56.8234, -47.4821) -> (56.42, -47.9049)
  line L1697 (57.1986, -47.0342) -> (56.8234, -47.4821)
  line L1698 (74.8143, -32.9237) -> (74.2432, -32.761)
  line L1699 (71.5085, -50.4821) -> (70.9269, -50.4266)
  line L1700 (79.4833, -36.4165) -> (79.1334, -35.9368)
  line L1701 (160.093, -50.5) -> (159.509, -50.4821)
  line L1702 (76.0585, -49.4711) -> (76.5813, -49.1896)
  line L1703 (79.9457, -36.9798) -> (80.2178, -37.4969)
  line L1704 (41.5618, -44.5156) -> (41.3817, -43.9597)
  line L1705 (151.159, -39.9096) -> (151.277, -39.3373)
  line L1706 (71.4521, -50.3832) -> (72.0455, -50.4049)
  line L1707 (58.5935, -44.2172) -> (58.7582, -43.6467)
  line L1708 (63.0612, -42.2388) -> (63.0291, -41.6553)
  line L1709 (52.3945, -50.0999) -> (52.9627, -49.9272)
  line L1710 (80.1527, -45.3193) -> (80.3914, -44.7756)
  line L1711 (58.084, -37.4403) -> (57.8006, -36.9185)
  line L1712 (66.7829, -34.1099) -> (67.2676, -33.7835)
  line L1713 (69.9488, -32.6538) -> (70.5208, -32.5348)
  line L1714 (42.2446, -45.7915) -> (42.5495, -46.301)
  line L1715 (80.3914, -44.7756) -> (80.5935, -44.2172)
  line L1716 (67.0175, -48.8389) -> (67.5183, -49.1579)
  line L1717 (157.78, -50.2038) -> (157.22, -50.0373)
  line L1718 (63.6834, -38.3285) -> (63.495, -38.8917)
  line L1719 (73.2302, -50.3304) -> (73.8162, -50.2345)
  line L1720 (41.1742, -42.4171) -> (41.2578, -43.005)
  line L1721 (77.2028, -33.9917) -> (77.6734, -34.338)
  line L1722 (159.099, -32.4529) -> (159.682, -32.4086)
  line L1723 (151.174, -42.4171) -> (151.258, -43.005)
  line L1724 (80.7806, -43.9293) -> (80.6024, -44.4858)
  line L1725 (63.9088, -37.7791) -> (63.6834, -38.3285)
  line L1726 (159.452, -50.3832) -> (160.046, -50.4049)
  line L1727 (71.682, -32.4086) -> (72.2663, -32.402)
  line L1728 (41.7392, -44.7175) -> (41.9741, -45.2629)
  line L1729 (46.5778, -49.6931) -> (47.1318, -49.9069)
  line L1730 (70.1233, -32.7107) -> (69.5484, -32.8593)
  line L1731 (72.0455, -50.4049) -> (72.6391, -50.3873)
  line L1732 (64.0276, -45.5867) -> (63.7774, -45.0587)
  line L1733 (63.0347, -41.071) -> (63.078, -40.4883)
  line L1734 (80.6024, -44.4858) -> (80.3887, -45.0297)
  line L1735 (70.2761, -50.2221) -> (70.8615, -50.3221)
  line L1736 (47.6987, -50.0835) -> (48.2761, -50.2221)
  line L1737 (41.0612, -42.2388) -> (41.0291, -41.6553)
  line L1738 (75.5182, -49.7173) -> (76.0585, -49.4711)
  line L1739 (74.5713, -32.7506) -> (75.1275, -32.9297)
  line L1740 (44.8893, -34.1505) -> (44.417, -34.5104)
  line L1741 (154.187, -48.3214) -> (153.756, -47.927)
  line L1742 (48.9269, -50.4266) -> (48.35, -50.3337)
  line L1743 (42.6274, -46.589) -> (42.3113, -46.0975)
  line L1744 (50.483, -32.5042) -> (49.8893, -32.497)
  line L1745 (48.1233, -32.7107) -> (47.5484, -32.8593)
  line L1746 (51.6626, -32.6365) -> (51.075, -32.5508)
  line L1747 (78.8557, -47.3014) -> (79.2286, -46.8393)
  line L1748 (65.157, -35.766) -> (64.7955, -36.2371)
  line L1749 (159.682, -32.4086) -> (160.266, -32.402)
  line L1750 (50.0926, -50.5) -> (49.5085, -50.4821)
  line L1751 (80.7582, -43.6467) -> (80.8847, -43.0665)
  line L1752 (68.4345, -33.2692) -> (67.9003, -33.5286)
  line L1753 (63.078, -40.4883) -> (63.1589, -39.9096)
  line L1754 (45.3845, -33.8228) -> (44.8893, -34.1505)
  line L1755 (72.8498, -32.4331) -> (73.4301, -32.5018)
  line L1756 (63.2379, -43.3934) -> (63.1309, -42.8189)
  line L1757 (80.9725, -42.4793) -> (81.0211, -41.8875)
  line L1758 (41.1245, -41.2312) -> (41.1297, -41.825)
  line L1759 (161.835, -50.3276) -> (161.258, -50.4226)
  line L1760 (79.3045, -36.0036) -> (79.6409, -36.4813)
  line L1761 (56.5428, -58.818) -> (56.9379, -59.2485)
  line L1762 (24.138, -49.5979) -> (23.6204, -49.3267)
  line L1763 (31.3734, -33.1239) -> (30.8143, -32.9237)
  line L1764 (145.229, -70.5393) -> (145.57, -70.0534)
  line L1765 (144.856, -71.0014) -> (145.229, -70.5393)
  line L1766 (146.153, -69.0193) -> (146.391, -68.4756)
  line L1767 (145.879, -69.546) -> (146.153, -69.0193)
  line L1768 (145.57, -70.0534) -> (145.879, -69.546)
  line L1769 (22.643, -48.6871) -> (22.1873, -48.3214)
  line L1770 (30.9627, -49.9272) -> (31.5182, -49.7173)
  line L1771 (36.8551, -39.68) -> (36.7185, -39.1021)
  line L1772 (58.7806, -67.6293) -> (58.6024, -68.1858)
  line L1773 (58.9224, -67.0625) -> (58.7806, -67.6293)
  line L1774 (58.1404, -69.2586) -> (57.8585, -69.7704)
  line L1775 (58.3887, -68.7297) -> (58.1404, -69.2586)
  line L1776 (58.6024, -68.1858) -> (58.3887, -68.7297)
  line L1777 (21.3513, -47.5056) -> (20.9746, -47.059)
  line L1778 (31.9179, -33.3606) -> (31.3734, -33.1239)
  line L1779 (20.7955, -36.2371) -> (20.466, -36.7311)
  line L1780 (52.9634, -73.7273) -> (52.4039, -73.8957)
  line L1781 (53.5109, -73.5231) -> (52.9634, -73.7273)
  line L1782 (51.2581, -74.1226) -> (50.6766, -74.1801)
  line L1783 (51.8346, -74.0276) -> (51.2581, -74.1226)
  line L1784 (52.4039, -73.8957) -> (51.8346, -74.0276)
  line L1785 (20.3113, -46.0975) -> (20.0276, -45.5867)
  line L1786 (33.5654, -48.5258) -> (34.0223, -48.1465)
  line L1787 (44.643, -72.3871) -> (44.1873, -72.0214)
  line L1788 (45.1214, -72.7227) -> (44.643, -72.3871)
  line L1789 (43.3513, -71.2056) -> (42.9746, -70.759)
  line L1790 (43.7561, -71.627) -> (43.3513, -71.2056)
  line L1791 (44.1873, -72.0214) -> (43.7561, -71.627)
  line L1792 (19.5618, -44.5156) -> (19.3817, -43.9597)
  line L1793 (36.9531, -40.2656) -> (36.8551, -39.68)
  line L1794 (20.466, -36.7311) -> (20.17, -37.2459)
  line L1795 (41.0332, -64.9312) -> (41.0347, -64.771)
  line L1796 (41.0291, -65.3553) -> (41.0332, -64.9312)
  line L1797 (41.2578, -66.705) -> (41.3803, -67.2861)
  line L1798 (41.1742, -66.1171) -> (41.2578, -66.705)
  line L1799 (41.0347, -64.771) -> (41.078, -64.1883)
  line L1800 (19.1309, -42.8189) -> (19.0612, -42.2388)
  line L1801 (20.17, -37.2459) -> (19.9088, -37.7791)
  line L1802 (19.495, -38.8917) -> (19.3443, -39.466)
  line L1803 (45.0175, -72.5389) -> (45.5183, -72.8579)
  line L1804 (44.539, -72.1873) -> (45.0175, -72.5389)
  line L1805 (46.5778, -73.3931) -> (47.1318, -73.6069)
  line L1806 (46.0392, -73.1431) -> (46.5778, -73.3931)
  line L1807 (45.5183, -72.8579) -> (46.0392, -73.1431)
  line L1808 (19.0332, -41.2312) -> (19.0347, -41.071)
  line L1809 (53.5182, -73.4173) -> (54.0585, -73.1711)
  line L1810 (52.9627, -73.6272) -> (53.5182, -73.4173)
  line L1811 (55.0844, -72.574) -> (55.5654, -72.2258)
  line L1812 (54.5813, -72.8896) -> (55.0844, -72.574)
  line L1813 (54.0585, -73.1711) -> (54.5813, -72.8896)
  line L1814 (19.2578, -43.005) -> (19.3803, -43.5861)
  line L1815 (19.6834, -38.3285) -> (19.495, -38.8917)
  line L1816 (19.9088, -37.7791) -> (19.6834, -38.3285)